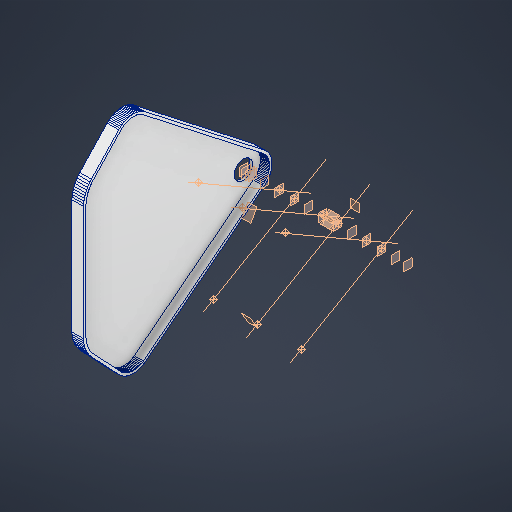
# Autodesk Inventor part: Timing_Cover
Saved by Autodesk Inventor 2027.1 (Build 311270010, 270A)
## iProperties
Created: 2026-10-17
Part Number: Timing_Cover
Material: Aluminum 6061
Document SubType Name: Modeling
Designer: kashyap
Density: 2.7 g/cm^3
Appearance: Aluminum - Flat
Mass: 3066.93 g
Surface Area: 3887.22 cm^2
Volume: 1135.9 cm^3
Material_Status: Assumed for this reconstruction
Author: kashyap
Autodesk Inventor part; units mm, degrees
ref_plane "YZ Plane" through (0, 0, 0) normal (1, 0, 0) x (0, 1, 0)
ref_plane "XZ Plane" through (0, 0, 0) normal (0, 1, 0) x (-1, 0, 0)
ref_plane "XY Plane" through (0, 0, 0) normal (0, 0, 1) x (1, 0, 0)
derived "V6_Engine_Master.ipt"
ref_plane "Bank_A_Plane" through (0, 0, 0) normal (0, 0.8660254, -0.5) x (-1, 0, 0)
ref_plane "Bank_B_Plane" through (0, 0, 0) normal (0, 0.8660254, 0.5) x (-1, 0, 0)
ref_plane "Bank_A_Perp_Plane" through (0, 0, 0) normal (0, 0.5, 0.8660254) x (-1, 0, 0)
ref_plane "Bank_B_Perp_Plane" through (0, 0, 0) normal (0, -0.5, 0.8660254) x (-1, 0, 0)
ref_plane "Bank_A_Deck_Plane" through (0, 112.9, 195.5485) normal (0, 0.5, 0.8660254) x (-1, 0, 0)
ref_plane "Bank_B_Deck_Plane" through (0, -112.9, 195.5485) normal (0, -0.5, 0.8660254) x (-1, 0, 0)
ref_plane "Cyl_A1_Station_Plane" through (-123.8, 0, 0) normal (1, 0, 0) x (0, 1, 0)
ref_plane "Cyl_A2_Station_Plane" through (-18.3, 0, 0) normal (1, 0, 0) x (0, 1, 0)
ref_plane "Cyl_A3_Station_Plane" through (87.2, 0, 0) normal (1, 0, 0) x (0, 1, 0)
ref_plane "Cyl_B1_Station_Plane" through (-87.2, 0, 0) normal (1, 0, 0) x (0, 1, 0)
ref_plane "Cyl_B2_Station_Plane" through (18.3, 0, 0) normal (1, 0, 0) x (0, 1, 0)
ref_plane "Cyl_B3_Station_Plane" through (123.8, 0, 0) normal (1, 0, 0) x (0, 1, 0)
ref_plane "Main_Bearing_Station_1" through (-158.25, 0, 0) normal (1, 0, 0) x (0, 1, 0)
ref_plane "Main_Bearing_Station_2" through (-52.75, 0, 0) normal (1, 0, 0) x (0, 1, 0)
ref_plane "Main_Bearing_Station_3" through (52.75, 0, 0) normal (1, 0, 0) x (0, 1, 0)
ref_plane "Main_Bearing_Station_4" through (158.25, 0, 0) normal (1, 0, 0) x (0, 1, 0)
ref_plane "Front_Interface" through (-188.25, 0, 0) normal (1, 0, 0) x (0, 1, 0)
ref_plane "Rear_Interface" through (188.25, 0, 0) normal (1, 0, 0) x (0, 1, 0)
ref_plane "Oil_Pan_Plane" through (0, 0, -60) normal (0, 0, 1) x (1, 0, 0)
ref_plane "Primary_Sprocket_Plane" through (-193.75, 0, 0) normal (1, 0, 0) x (0, 1, 0)
ref_plane "Secondary_Sprocket_Plane" through (-203.75, 0, 0) normal (1, 0, 0) x (0, 1, 0)
ref_plane "Cover_Inner_Plane" through (-210.25, 0, 0) normal (1, 0, 0) x (0, 1, 0)
sketch "SK_Cover_Plate" plane through (-210.25, 0, 0) normal (1, 0, 0) x (0, 1, 0)
  line L0 (-272.0577, 288.2542) -> (-271.9422, 284.9459)
  line L1 (-271.9422, 284.9459) -> (-271.5962, 281.6538)
  line L2 (-271.5962, 281.6538) -> (-271.0214, 278.3938)
  line L3 (-271.0214, 278.3938) -> (-270.2205, 275.1818)
  line L4 (-270.2205, 275.1818) -> (-269.1976, 272.0335)
  line L5 (-269.1976, 272.0335) -> (-267.9575, 268.9643)
  line L6 (-267.9575, 268.9643) -> (-266.5064, 265.989)
  line L7 (-266.5064, 265.989) -> (-264.8512, 263.1222)
  line L8 (-264.8512, 263.1222) -> (-263.0001, 260.3778)
  line L9 (-263.0001, 260.3778) -> (-38.3686, -27.8764)
  line L10 (-38.3686, -27.8764) -> (-36.3305, -30.4849)
  line L11 (-36.3305, -30.4849) -> (-34.1155, -32.945)
  line L12 (-34.1155, -32.945) -> (-31.7343, -35.2445)
  line L13 (-31.7343, -35.2445) -> (-29.1985, -37.3723)
  line L14 (-29.1985, -37.3723) -> (-26.5204, -39.3181)
  line L15 (-26.5204, -39.3181) -> (-23.7131, -41.0722)
  line L16 (-23.7131, -41.0722) -> (-20.7903, -42.6263)
  line L17 (-20.7903, -42.6263) -> (-17.7661, -43.9728)
  line L18 (-17.7661, -43.9728) -> (-14.6555, -45.1049)
  line L19 (-14.6555, -45.1049) -> (-11.4734, -46.0174)
  line L20 (-11.4734, -46.0174) -> (-8.2355, -46.7056)
  line L21 (-8.2355, -46.7056) -> (-4.9574, -47.1663)
  line L22 (-4.9574, -47.1663) -> (-1.6551, -47.3973)
  line L23 (-1.6551, -47.3973) -> (1.6551, -47.3973)
  line L24 (1.6551, -47.3973) -> (4.9574, -47.1663)
  line L25 (4.9574, -47.1663) -> (8.2355, -46.7056)
  line L26 (8.2355, -46.7056) -> (11.4734, -46.0174)
  line L27 (11.4734, -46.0174) -> (14.6555, -45.1049)
  line L28 (14.6555, -45.1049) -> (17.7661, -43.9728)
  line L29 (17.7661, -43.9728) -> (20.7903, -42.6263)
  line L30 (20.7903, -42.6263) -> (23.7131, -41.0722)
  line L31 (23.7131, -41.0722) -> (26.5204, -39.3181)
  line L32 (26.5204, -39.3181) -> (29.1985, -37.3723)
  line L33 (29.1985, -37.3723) -> (31.7343, -35.2445)
  line L34 (31.7343, -35.2445) -> (34.1155, -32.945)
  line L35 (34.1155, -32.945) -> (36.3305, -30.4849)
  line L36 (36.3305, -30.4849) -> (38.3686, -27.8764)
  line L37 (38.3686, -27.8764) -> (263.0001, 260.3778)
  line L38 (263.0001, 260.3778) -> (264.8512, 263.1222)
  line L39 (264.8512, 263.1222) -> (266.5064, 265.989)
  line L40 (266.5064, 265.989) -> (267.9575, 268.9643)
  line L41 (267.9575, 268.9643) -> (269.1976, 272.0335)
  line L42 (269.1976, 272.0335) -> (270.2205, 275.1818)
  line L43 (270.2205, 275.1818) -> (271.0214, 278.3938)
  line L44 (271.0214, 278.3938) -> (271.5962, 281.6538)
  line L45 (271.5962, 281.6538) -> (271.9422, 284.9459)
  line L46 (271.9422, 284.9459) -> (272.0577, 288.2542)
  line L47 (272.0577, 288.2542) -> (271.9422, 291.5625)
  line L48 (271.9422, 291.5625) -> (271.5962, 294.8547)
  line L49 (271.5962, 294.8547) -> (271.0214, 298.1147)
  line L50 (271.0214, 298.1147) -> (270.2205, 301.3266)
  line L51 (270.2205, 301.3266) -> (269.1976, 304.4749)
  line L52 (269.1976, 304.4749) -> (267.9575, 307.5442)
  line L53 (267.9575, 307.5442) -> (266.5064, 310.5194)
  line L54 (266.5064, 310.5194) -> (264.8512, 313.3862)
  line L55 (264.8512, 313.3862) -> (263.0001, 316.1306)
  line L56 (263.0001, 316.1306) -> (260.9621, 318.7391)
  line L57 (260.9621, 318.7391) -> (258.7471, 321.1992)
  line L58 (258.7471, 321.1992) -> (256.3659, 323.4987)
  line L59 (256.3659, 323.4987) -> (186.012, 389.7609)
  line L60 (186.012, 389.7609) -> (182.0208, 393.1099)
  line L61 (182.0208, 393.1099) -> (177.8058, 396.1723)
  line L62 (177.8058, 396.1723) -> (173.3874, 398.9332)
  line L63 (173.3874, 398.9332) -> (168.7872, 401.3792)
  line L64 (168.7872, 401.3792) -> (164.0276, 403.4983)
  line L65 (164.0276, 403.4983) -> (159.1318, 405.2802)
  line L66 (159.1318, 405.2802) -> (154.1236, 406.7163)
  line L67 (154.1236, 406.7163) -> (149.0274, 407.7995)
  line L68 (149.0274, 407.7995) -> (143.868, 408.5246)
  line L69 (143.868, 408.5246) -> (138.6707, 408.8881)
  line L70 (138.6707, 408.8881) -> (-138.6707, 408.8881)
  line L71 (-138.6707, 408.8881) -> (-143.868, 408.5246)
  line L72 (-143.868, 408.5246) -> (-149.0274, 407.7995)
  line L73 (-149.0274, 407.7995) -> (-154.1236, 406.7163)
  line L74 (-154.1236, 406.7163) -> (-159.1318, 405.2802)
  line L75 (-159.1318, 405.2802) -> (-164.0276, 403.4983)
  line L76 (-164.0276, 403.4983) -> (-168.7872, 401.3792)
  line L77 (-168.7872, 401.3792) -> (-173.3874, 398.9332)
  line L78 (-173.3874, 398.9332) -> (-177.8058, 396.1723)
  line L79 (-177.8058, 396.1723) -> (-182.0208, 393.1099)
  line L80 (-182.0208, 393.1099) -> (-186.012, 389.7609)
  line L81 (-186.012, 389.7609) -> (-256.3659, 323.4987)
  line L82 (-256.3659, 323.4987) -> (-258.7471, 321.1992)
  line L83 (-258.7471, 321.1992) -> (-260.9621, 318.7391)
  line L84 (-260.9621, 318.7391) -> (-263.0001, 316.1306)
  line L85 (-263.0001, 316.1306) -> (-264.8512, 313.3862)
  line L86 (-264.8512, 313.3862) -> (-266.5064, 310.5194)
  line L87 (-266.5064, 310.5194) -> (-267.9575, 307.5442)
  line L88 (-267.9575, 307.5442) -> (-269.1976, 304.4749)
  line L89 (-269.1976, 304.4749) -> (-270.2205, 301.3266)
  line L90 (-270.2205, 301.3266) -> (-271.0214, 298.1147)
  line L91 (-271.0214, 298.1147) -> (-271.5962, 294.8547)
  line L92 (-271.5962, 294.8547) -> (-271.9422, 291.5625)
  line L93 (-271.9422, 291.5625) -> (-272.0577, 288.2542)
  constraints: 188 end point
extrude "Cover_Plate_SIMPLIFIED" add sketch "SK_Cover_Plate" against normal blind 6
sketch "SK_Cover_Rim" plane through (-210.25, 0, 0) normal (1, 0, 0) x (0, 1, 0)
  line L0 (-272.0577, 288.2542) -> (-271.9422, 284.9459)
  line L1 (-271.9422, 284.9459) -> (-271.5962, 281.6538)
  line L2 (-271.5962, 281.6538) -> (-271.0214, 278.3938)
  line L3 (-271.0214, 278.3938) -> (-270.2205, 275.1818)
  line L4 (-270.2205, 275.1818) -> (-269.1976, 272.0335)
  line L5 (-269.1976, 272.0335) -> (-267.9575, 268.9643)
  line L6 (-267.9575, 268.9643) -> (-266.5064, 265.989)
  line L7 (-266.5064, 265.989) -> (-264.8512, 263.1222)
  line L8 (-264.8512, 263.1222) -> (-263.0001, 260.3778)
  line L9 (-263.0001, 260.3778) -> (-38.3686, -27.8764)
  line L10 (-38.3686, -27.8764) -> (-36.3305, -30.4849)
  line L11 (-36.3305, -30.4849) -> (-34.1155, -32.945)
  line L12 (-34.1155, -32.945) -> (-31.7343, -35.2445)
  line L13 (-31.7343, -35.2445) -> (-29.1985, -37.3723)
  line L14 (-29.1985, -37.3723) -> (-26.5204, -39.3181)
  line L15 (-26.5204, -39.3181) -> (-23.7131, -41.0722)
  line L16 (-23.7131, -41.0722) -> (-20.7903, -42.6263)
  line L17 (-20.7903, -42.6263) -> (-17.7661, -43.9728)
  line L18 (-17.7661, -43.9728) -> (-14.6555, -45.1049)
  line L19 (-14.6555, -45.1049) -> (-11.4734, -46.0174)
  line L20 (-11.4734, -46.0174) -> (-8.2355, -46.7056)
  line L21 (-8.2355, -46.7056) -> (-4.9574, -47.1663)
  line L22 (-4.9574, -47.1663) -> (-1.6551, -47.3973)
  line L23 (-1.6551, -47.3973) -> (1.6551, -47.3973)
  line L24 (1.6551, -47.3973) -> (4.9574, -47.1663)
  line L25 (4.9574, -47.1663) -> (8.2355, -46.7056)
  line L26 (8.2355, -46.7056) -> (11.4734, -46.0174)
  line L27 (11.4734, -46.0174) -> (14.6555, -45.1049)
  line L28 (14.6555, -45.1049) -> (17.7661, -43.9728)
  line L29 (17.7661, -43.9728) -> (20.7903, -42.6263)
  line L30 (20.7903, -42.6263) -> (23.7131, -41.0722)
  line L31 (23.7131, -41.0722) -> (26.5204, -39.3181)
  line L32 (26.5204, -39.3181) -> (29.1985, -37.3723)
  line L33 (29.1985, -37.3723) -> (31.7343, -35.2445)
  line L34 (31.7343, -35.2445) -> (34.1155, -32.945)
  line L35 (34.1155, -32.945) -> (36.3305, -30.4849)
  line L36 (36.3305, -30.4849) -> (38.3686, -27.8764)
  line L37 (38.3686, -27.8764) -> (263.0001, 260.3778)
  line L38 (263.0001, 260.3778) -> (264.8512, 263.1222)
  line L39 (264.8512, 263.1222) -> (266.5064, 265.989)
  line L40 (266.5064, 265.989) -> (267.9575, 268.9643)
  line L41 (267.9575, 268.9643) -> (269.1976, 272.0335)
  line L42 (269.1976, 272.0335) -> (270.2205, 275.1818)
  line L43 (270.2205, 275.1818) -> (271.0214, 278.3938)
  line L44 (271.0214, 278.3938) -> (271.5962, 281.6538)
  line L45 (271.5962, 281.6538) -> (271.9422, 284.9459)
  line L46 (271.9422, 284.9459) -> (272.0577, 288.2542)
  line L47 (272.0577, 288.2542) -> (271.9422, 291.5625)
  line L48 (271.9422, 291.5625) -> (271.5962, 294.8547)
  line L49 (271.5962, 294.8547) -> (271.0214, 298.1147)
  line L50 (271.0214, 298.1147) -> (270.2205, 301.3266)
  line L51 (270.2205, 301.3266) -> (269.1976, 304.4749)
  line L52 (269.1976, 304.4749) -> (267.9575, 307.5442)
  line L53 (267.9575, 307.5442) -> (266.5064, 310.5194)
  line L54 (266.5064, 310.5194) -> (264.8512, 313.3862)
  line L55 (264.8512, 313.3862) -> (263.0001, 316.1306)
  line L56 (263.0001, 316.1306) -> (260.9621, 318.7391)
  line L57 (260.9621, 318.7391) -> (258.7471, 321.1992)
  line L58 (258.7471, 321.1992) -> (256.3659, 323.4987)
  line L59 (256.3659, 323.4987) -> (186.012, 389.7609)
  line L60 (186.012, 389.7609) -> (182.0208, 393.1099)
  line L61 (182.0208, 393.1099) -> (177.8058, 396.1723)
  line L62 (177.8058, 396.1723) -> (173.3874, 398.9332)
  line L63 (173.3874, 398.9332) -> (168.7872, 401.3792)
  line L64 (168.7872, 401.3792) -> (164.0276, 403.4983)
  line L65 (164.0276, 403.4983) -> (159.1318, 405.2802)
  line L66 (159.1318, 405.2802) -> (154.1236, 406.7163)
  line L67 (154.1236, 406.7163) -> (149.0274, 407.7995)
  line L68 (149.0274, 407.7995) -> (143.868, 408.5246)
  line L69 (143.868, 408.5246) -> (138.6707, 408.8881)
  line L70 (138.6707, 408.8881) -> (-138.6707, 408.8881)
  line L71 (-138.6707, 408.8881) -> (-143.868, 408.5246)
  line L72 (-143.868, 408.5246) -> (-149.0274, 407.7995)
  line L73 (-149.0274, 407.7995) -> (-154.1236, 406.7163)
  line L74 (-154.1236, 406.7163) -> (-159.1318, 405.2802)
  line L75 (-159.1318, 405.2802) -> (-164.0276, 403.4983)
  line L76 (-164.0276, 403.4983) -> (-168.7872, 401.3792)
  line L77 (-168.7872, 401.3792) -> (-173.3874, 398.9332)
  line L78 (-173.3874, 398.9332) -> (-177.8058, 396.1723)
  line L79 (-177.8058, 396.1723) -> (-182.0208, 393.1099)
  line L80 (-182.0208, 393.1099) -> (-186.012, 389.7609)
  line L81 (-186.012, 389.7609) -> (-256.3659, 323.4987)
  line L82 (-256.3659, 323.4987) -> (-258.7471, 321.1992)
  line L83 (-258.7471, 321.1992) -> (-260.9621, 318.7391)
  line L84 (-260.9621, 318.7391) -> (-263.0001, 316.1306)
  line L85 (-263.0001, 316.1306) -> (-264.8512, 313.3862)
  line L86 (-264.8512, 313.3862) -> (-266.5064, 310.5194)
  line L87 (-266.5064, 310.5194) -> (-267.9575, 307.5442)
  line L88 (-267.9575, 307.5442) -> (-269.1976, 304.4749)
  line L89 (-269.1976, 304.4749) -> (-270.2205, 301.3266)
  line L90 (-270.2205, 301.3266) -> (-271.0214, 298.1147)
  line L91 (-271.0214, 298.1147) -> (-271.5962, 294.8547)
  line L92 (-271.5962, 294.8547) -> (-271.9422, 291.5625)
  line L93 (-271.9422, 291.5625) -> (-272.0577, 288.2542)
  line L94 (-266.0577, 288.2542) -> (-265.9568, 285.3645)
  line L95 (-265.9568, 285.3645) -> (-265.6546, 282.4888)
  line L96 (-265.6546, 282.4888) -> (-265.1525, 279.6412)
  line L97 (-265.1525, 279.6412) -> (-264.4529, 276.8356)
  line L98 (-264.4529, 276.8356) -> (-263.5594, 274.0856)
  line L99 (-263.5594, 274.0856) -> (-262.4762, 271.4047)
  line L100 (-262.4762, 271.4047) -> (-261.2087, 268.8058)
  line L101 (-261.2087, 268.8058) -> (-259.7629, 266.3017)
  line L102 (-259.7629, 266.3017) -> (-258.146, 263.9045)
  line L103 (-258.146, 263.9045) -> (-33.5145, -24.3497)
  line L104 (-33.5145, -24.3497) -> (-31.7343, -26.6282)
  line L105 (-31.7343, -26.6282) -> (-29.7995, -28.777)
  line L106 (-29.7995, -28.777) -> (-27.7195, -30.7856)
  line L107 (-27.7195, -30.7856) -> (-25.5045, -32.6442)
  line L108 (-25.5045, -32.6442) -> (-23.1652, -34.3438)
  line L109 (-23.1652, -34.3438) -> (-20.7131, -35.8761)
  line L110 (-20.7131, -35.8761) -> (-18.16, -37.2336)
  line L111 (-18.16, -37.2336) -> (-15.5185, -38.4097)
  line L112 (-15.5185, -38.4097) -> (-12.8014, -39.3986)
  line L113 (-12.8014, -39.3986) -> (-10.0219, -40.1956)
  line L114 (-10.0219, -40.1956) -> (-7.1936, -40.7968)
  line L115 (-7.1936, -40.7968) -> (-4.3302, -41.1992)
  line L116 (-4.3302, -41.1992) -> (-1.4458, -41.4009)
  line L117 (-1.4458, -41.4009) -> (1.4458, -41.4009)
  line L118 (1.4458, -41.4009) -> (4.3302, -41.1992)
  line L119 (4.3302, -41.1992) -> (7.1936, -40.7968)
  line L120 (7.1936, -40.7968) -> (10.0219, -40.1956)
  line L121 (10.0219, -40.1956) -> (12.8014, -39.3986)
  line L122 (12.8014, -39.3986) -> (15.5185, -38.4097)
  line L123 (15.5185, -38.4097) -> (18.16, -37.2336)
  line L124 (18.16, -37.2336) -> (20.7131, -35.8761)
  line L125 (20.7131, -35.8761) -> (23.1652, -34.3438)
  line L126 (23.1652, -34.3438) -> (25.5045, -32.6442)
  line L127 (25.5045, -32.6442) -> (27.7195, -30.7856)
  line L128 (27.7195, -30.7856) -> (29.7995, -28.777)
  line L129 (29.7995, -28.777) -> (31.7343, -26.6282)
  line L130 (31.7343, -26.6282) -> (33.5145, -24.3497)
  line L131 (33.5145, -24.3497) -> (258.146, 263.9045)
  line L132 (258.146, 263.9045) -> (259.7629, 266.3017)
  line L133 (259.7629, 266.3017) -> (261.2087, 268.8058)
  line L134 (261.2087, 268.8058) -> (262.4762, 271.4047)
  line L135 (262.4762, 271.4047) -> (263.5594, 274.0856)
  line L136 (263.5594, 274.0856) -> (264.4529, 276.8356)
  line L137 (264.4529, 276.8356) -> (265.1525, 279.6412)
  line L138 (265.1525, 279.6412) -> (265.6546, 282.4888)
  line L139 (265.6546, 282.4888) -> (265.9568, 285.3645)
  line L140 (265.9568, 285.3645) -> (266.0577, 288.2542)
  line L141 (266.0577, 288.2542) -> (265.9568, 291.1439)
  line L142 (265.9568, 291.1439) -> (265.6546, 294.0196)
  line L143 (265.6546, 294.0196) -> (265.1525, 296.8672)
  line L144 (265.1525, 296.8672) -> (264.4529, 299.6728)
  line L145 (264.4529, 299.6728) -> (263.5594, 302.4228)
  line L146 (263.5594, 302.4228) -> (262.4762, 305.1037)
  line L147 (262.4762, 305.1037) -> (261.2087, 307.7026)
  line L148 (261.2087, 307.7026) -> (259.7629, 310.2067)
  line L149 (259.7629, 310.2067) -> (258.146, 312.6039)
  line L150 (258.146, 312.6039) -> (256.3659, 314.8824)
  line L151 (256.3659, 314.8824) -> (254.4311, 317.0312)
  line L152 (254.4311, 317.0312) -> (252.3511, 319.0398)
  line L153 (252.3511, 319.0398) -> (181.9972, 385.3021)
  line L154 (181.9972, 385.3021) -> (178.3269, 388.3818)
  line L155 (178.3269, 388.3818) -> (174.4507, 391.1981)
  line L156 (174.4507, 391.1981) -> (170.3874, 393.737)
  line L157 (170.3874, 393.737) -> (166.157, 395.9864)
  line L158 (166.157, 395.9864) -> (161.78, 397.9352)
  line L159 (161.78, 397.9352) -> (157.2777, 399.5739)
  line L160 (157.2777, 399.5739) -> (152.672, 400.8945)
  line L161 (152.672, 400.8945) -> (147.9855, 401.8907)
  line L162 (147.9855, 401.8907) -> (143.2409, 402.5575)
  line L163 (143.2409, 402.5575) -> (138.4613, 402.8917)
  line L164 (138.4613, 402.8917) -> (-138.4613, 402.8917)
  line L165 (-138.4613, 402.8917) -> (-143.2409, 402.5575)
  line L166 (-143.2409, 402.5575) -> (-147.9855, 401.8907)
  line L167 (-147.9855, 401.8907) -> (-152.672, 400.8945)
  line L168 (-152.672, 400.8945) -> (-157.2777, 399.5739)
  line L169 (-157.2777, 399.5739) -> (-161.78, 397.9352)
  line L170 (-161.78, 397.9352) -> (-166.157, 395.9864)
  line L171 (-166.157, 395.9864) -> (-170.3874, 393.737)
  line L172 (-170.3874, 393.737) -> (-174.4507, 391.1981)
  line L173 (-174.4507, 391.1981) -> (-178.3269, 388.3818)
  line L174 (-178.3269, 388.3818) -> (-181.9972, 385.3021)
  line L175 (-181.9972, 385.3021) -> (-252.3511, 319.0398)
  line L176 (-252.3511, 319.0398) -> (-254.4311, 317.0312)
  line L177 (-254.4311, 317.0312) -> (-256.3659, 314.8824)
  line L178 (-256.3659, 314.8824) -> (-258.146, 312.6039)
  line L179 (-258.146, 312.6039) -> (-259.7629, 310.2067)
  line L180 (-259.7629, 310.2067) -> (-261.2087, 307.7026)
  line L181 (-261.2087, 307.7026) -> (-262.4762, 305.1037)
  line L182 (-262.4762, 305.1037) -> (-263.5594, 302.4228)
  line L183 (-263.5594, 302.4228) -> (-264.4529, 299.6728)
  line L184 (-264.4529, 299.6728) -> (-265.1525, 296.8672)
  line L185 (-265.1525, 296.8672) -> (-265.6546, 294.0196)
  line L186 (-265.6546, 294.0196) -> (-265.9568, 291.1439)
  line L187 (-265.9568, 291.1439) -> (-266.0577, 288.2542)
  constraints: 376 end point
extrude "Cover_Rim_SIMPLIFIED" add sketch "SK_Cover_Rim" along normal blind 22
sketch "SK_Crank_Hole" plane through (-210.25, 0, 0) normal (1, 0, 0) x (0, 1, 0)
  circle A0 centre (0, 0) radius 22.5
  dimension "d28" = 45
  constraints: 1 centre point
  measures "d28" diameter of A0
extrude "Crank_Snout_Hole" cut sketch "SK_Crank_Hole" against normal blind 7
equation "\"d24\" = Timing_Cover_Thickness"
equation "\"d26\" = Timing_Cover_Gap"
equation "\"Timing_Cover_Thickness\" = 6"
equation "\"Timing_Cover_Gap\" = 22"
body "Solid2"
